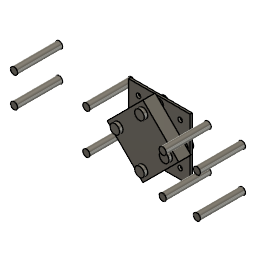
BGD_AIO_ENVELOPE_R3_NOT_FOR_FABRICATION (Autodesk Fusion 360 design; units mm, degrees)
part number: 2026-09-05-21-45-48-838
part number: 2026-09-05-21-45-49-225
part number: 2026-09-05-21-45-49-322
part number: 2026-09-05-21-45-49-390
part number: 2026-09-05-21-45-49-432
part number: 2026-09-05-21-45-49-478
part number: 2026-09-05-21-45-49-524
part number: 2026-09-05-21-45-49-562
part number: 2026-09-05-21-45-49-626
part number: 2026-09-05-21-45-49-709
part number: 2026-09-05-21-45-49-758
part number: 2026-09-05-21-45-49-811
part number: 2026-09-05-21-45-49-877
part number: 2026-09-05-21-45-49-921
part number: 2026-09-05-21-45-49-965
part number: 2026-09-05-21-45-50-016
part number: 2026-09-05-21-45-50-060
part number: 2026-09-05-21-45-50-111
part number: 2026-09-05-21-45-50-153
part number: 2026-09-05-21-45-50-197
part number: 2026-09-05-21-45-50-263
part number: 2026-09-05-21-45-50-331
part number: 2026-09-05-21-45-50-419
part number: 2026-09-05-21-45-50-495
part number: 2026-09-05-21-45-50-578
part number: 2026-09-05-21-45-50-662
part number: 2026-09-05-21-45-50-760
part number: 2026-09-05-21-45-50-872
Autodesk Fusion 360 part; units mm, degrees
sketch "Sketch1" plane through (0, 0, 0) normal (0, 0, 1) x (1, 0, 0) in component "R3_45mm_ADAPTER_NOMINAL_DRILLING_HOLD"
  line L0 (-22.5, -22.5) -> (22.5, -22.5)
  line L1 (22.5, -22.5) -> (22.5, 22.5)
  line L2 (22.5, 22.5) -> (-22.5, 22.5)
  line L3 (-22.5, 22.5) -> (-22.5, -22.5)
  circle A0 centre (-15.25, -15.25) radius 1.6
  circle A1 centre (-15.25, 15.25) radius 1.6
  circle A2 centre (15.25, -15.25) radius 1.6
  circle A3 centre (15.25, 15.25) radius 1.6
  circle A4 centre (18.0312, 0) radius 1.6
  circle A5 centre (-18.0312, 0) radius 1.6
  circle A6 centre (0, 18.0312) radius 1.6
  circle A7 centre (0, -18.0312) radius 1.6
extrude "Extrude1" add sketch "Sketch1" along normal blind 1.6 makes body 1 in component "R3_45mm_ADAPTER_NOMINAL_DRILLING_HOLD"
sketch "Sketch1 (2)" plane through (0, 0, 0) normal (0, 0, 1) x (1, 0, 0) in component "AIO_MAX_37x37x9_CLASS4_ENVELOPE"
  line L0 (-18.5, -18.5) -> (18.5, -18.5)
  line L1 (18.5, -18.5) -> (18.5, 18.5)
  line L2 (18.5, 18.5) -> (-18.5, 18.5)
  line L3 (-18.5, 18.5) -> (-18.5, -18.5)
  circle A0 centre (-12.75, -12.75) radius 1.5
  circle A1 centre (-12.75, 12.75) radius 1.5
  circle A2 centre (12.75, -12.75) radius 1.5
  circle A3 centre (12.75, 12.75) radius 1.5
extrude "Extrude1'" add sketch "Sketch1 (2)" along normal blind 9 separate body makes body 2 in component "AIO_MAX_37x37x9_CLASS4_ENVELOPE"
sketch "Sketch1 (3)" plane through (0, 0, 0) normal (0, 0, 1) x (1, 0, 0) in component "ISOLATOR_0_OD6_RISE3_CONTRACT_ONLY"
  circle A0 centre (0, 0) radius 3
extrude "Extrude1''" add sketch "Sketch1 (3)" along normal blind 3 separate body makes body 3 in component "ISOLATOR_0_OD6_RISE3_CONTRACT_ONLY"
sketch "Sketch1 (4)" plane through (0, 0, 0) normal (0, 0, 1) x (1, 0, 0) in component "FASTENER_TOP_0_PROJECTION_CONTRACT_ONLY"
  circle A0 centre (0, 0) radius 3.5
extrude "Extrude1'''" add sketch "Sketch1 (4)" along normal blind 2.5 separate body makes body 4 in component "FASTENER_TOP_0_PROJECTION_CONTRACT_ONLY"
sketch "Sketch1 (5)" plane through (0, 0, 0) normal (0, 0, 1) x (1, 0, 0) in component "FASTENER_UNDER_0_PROJECTION_CONTRACT_ONLY"
  circle A0 centre (0, 0) radius 3.5
extrude "Extrude1''''" add sketch "Sketch1 (5)" along normal blind 2 separate body makes body 5 in component "FASTENER_UNDER_0_PROJECTION_CONTRACT_ONLY"
sketch "Sketch1 (6)" plane through (0, 0, 0) normal (0, 0, 1) x (1, 0, 0) in component "ISOLATOR_1_OD6_RISE3_CONTRACT_ONLY"
  circle A0 centre (0, 0) radius 3
extrude "Extrude1'''''" add sketch "Sketch1 (6)" along normal blind 3 separate body makes body 6 in component "ISOLATOR_1_OD6_RISE3_CONTRACT_ONLY"
sketch "Sketch1 (7)" plane through (0, 0, 0) normal (0, 0, 1) x (1, 0, 0) in component "FASTENER_TOP_1_PROJECTION_CONTRACT_ONLY"
  circle A0 centre (0, 0) radius 3.5
extrude "Extrude1''''''" add sketch "Sketch1 (7)" along normal blind 2.5 separate body makes body 7 in component "FASTENER_TOP_1_PROJECTION_CONTRACT_ONLY"
sketch "Sketch1 (8)" plane through (0, 0, 0) normal (0, 0, 1) x (1, 0, 0) in component "FASTENER_UNDER_1_PROJECTION_CONTRACT_ONLY"
  circle A0 centre (0, 0) radius 3.5
extrude "Extrude1'''''''" add sketch "Sketch1 (8)" along normal blind 2 separate body makes body 8 in component "FASTENER_UNDER_1_PROJECTION_CONTRACT_ONLY"
sketch "Sketch1 (9)" plane through (0, 0, 0) normal (0, 0, 1) x (1, 0, 0) in component "ISOLATOR_2_OD6_RISE3_CONTRACT_ONLY"
  circle A0 centre (0, 0) radius 3
extrude "Extrude1''''''''" add sketch "Sketch1 (9)" along normal blind 3 separate body makes body 9 in component "ISOLATOR_2_OD6_RISE3_CONTRACT_ONLY"
sketch "Sketch1 (10)" plane through (0, 0, 0) normal (0, 0, 1) x (1, 0, 0) in component "FASTENER_TOP_2_PROJECTION_CONTRACT_ONLY"
  circle A0 centre (0, 0) radius 3.5
extrude "Extrude1'''''''''" add sketch "Sketch1 (10)" along normal blind 2.5 separate body makes body 10 in component "FASTENER_TOP_2_PROJECTION_CONTRACT_ONLY"
sketch "Sketch1 (11)" plane through (0, 0, 0) normal (0, 0, 1) x (1, 0, 0) in component "FASTENER_UNDER_2_PROJECTION_CONTRACT_ONLY"
  circle A0 centre (0, 0) radius 3.5
extrude "Extrude1''''''''''" add sketch "Sketch1 (11)" along normal blind 2 separate body makes body 11 in component "FASTENER_UNDER_2_PROJECTION_CONTRACT_ONLY"
sketch "Sketch1 (12)" plane through (0, 0, 0) normal (0, 0, 1) x (1, 0, 0) in component "ISOLATOR_3_OD6_RISE3_CONTRACT_ONLY"
  circle A0 centre (0, 0) radius 3
extrude "Extrude1'''''''''''" add sketch "Sketch1 (12)" along normal blind 3 separate body makes body 12 in component "ISOLATOR_3_OD6_RISE3_CONTRACT_ONLY"
sketch "Sketch1 (13)" plane through (0, 0, 0) normal (0, 0, 1) x (1, 0, 0) in component "FASTENER_TOP_3_PROJECTION_CONTRACT_ONLY"
  circle A0 centre (0, 0) radius 3.5
extrude "Extrude1''''''''''''" add sketch "Sketch1 (13)" along normal blind 2.5 separate body makes body 13 in component "FASTENER_TOP_3_PROJECTION_CONTRACT_ONLY"
sketch "Sketch1 (14)" plane through (0, 0, 0) normal (0, 0, 1) x (1, 0, 0) in component "FASTENER_UNDER_3_PROJECTION_CONTRACT_ONLY"
  circle A0 centre (0, 0) radius 3.5
extrude "Extrude1'''''''''''''" add sketch "Sketch1 (14)" along normal blind 2 separate body makes body 14 in component "FASTENER_UNDER_3_PROJECTION_CONTRACT_ONLY"
sketch "Sketch1 (15)" plane through (0, 0, 0) normal (0, 0, 1) x (1, 0, 0) in component "FRAME_SUPPORT_0_OD5_2_ENVELOPE"
  circle A0 centre (0, 0) radius 2.6
extrude "Extrude1''''''''''''''" add sketch "Sketch1 (15)" along normal blind 33 separate body makes body 15 in component "FRAME_SUPPORT_0_OD5_2_ENVELOPE"
sketch "Sketch1 (16)" plane through (0, 0, 0) normal (0, 0, 1) x (1, 0, 0) in component "FRAME_SUPPORT_1_OD5_2_ENVELOPE"
  circle A0 centre (0, 0) radius 2.6
extrude "Extrude1'''''''''''''''" add sketch "Sketch1 (16)" along normal blind 33 separate body makes body 16 in component "FRAME_SUPPORT_1_OD5_2_ENVELOPE"
sketch "Sketch1 (17)" plane through (0, 0, 0) normal (0, 0, 1) x (1, 0, 0) in component "FRAME_SUPPORT_2_OD5_2_ENVELOPE"
  circle A0 centre (0, 0) radius 2.6
extrude "Extrude1''''''''''''''''" add sketch "Sketch1 (17)" along normal blind 33 separate body makes body 17 in component "FRAME_SUPPORT_2_OD5_2_ENVELOPE"
sketch "Sketch1 (18)" plane through (0, 0, 0) normal (0, 0, 1) x (1, 0, 0) in component "FRAME_SUPPORT_3_OD5_2_ENVELOPE"
  circle A0 centre (0, 0) radius 2.6
extrude "Extrude1'''''''''''''''''" add sketch "Sketch1 (18)" along normal blind 33 separate body makes body 18 in component "FRAME_SUPPORT_3_OD5_2_ENVELOPE"
sketch "Sketch1 (19)" plane through (0, 0, 0) normal (0, 0, 1) x (1, 0, 0) in component "FRAME_SUPPORT_4_OD5_2_ENVELOPE"
  circle A0 centre (0, 0) radius 2.6
extrude "Extrude1''''''''''''''''''" add sketch "Sketch1 (19)" along normal blind 33 separate body makes body 19 in component "FRAME_SUPPORT_4_OD5_2_ENVELOPE"
sketch "Sketch1 (20)" plane through (0, 0, 0) normal (0, 0, 1) x (1, 0, 0) in component "FRAME_SUPPORT_5_OD5_2_ENVELOPE"
  circle A0 centre (0, 0) radius 2.6
extrude "Extrude1'''''''''''''''''''" add sketch "Sketch1 (20)" along normal blind 33 separate body makes body 20 in component "FRAME_SUPPORT_5_OD5_2_ENVELOPE"
sketch "Sketch1 (21)" plane through (0, 0, 0) normal (0, 0, 1) x (1, 0, 0) in component "FRAME_SUPPORT_6_OD5_2_ENVELOPE"
  circle A0 centre (0, 0) radius 2.6
extrude "Extrude1''''''''''''''''''''" add sketch "Sketch1 (21)" along normal blind 33 separate body makes body 21 in component "FRAME_SUPPORT_6_OD5_2_ENVELOPE"
sketch "Sketch1 (22)" plane through (0, 0, 0) normal (0, 0, 1) x (1, 0, 0) in component "FRAME_SUPPORT_7_OD5_2_ENVELOPE"
  circle A0 centre (0, 0) radius 2.6
extrude "Extrude1'''''''''''''''''''''" add sketch "Sketch1 (22)" along normal blind 33 separate body makes body 22 in component "FRAME_SUPPORT_7_OD5_2_ENVELOPE"
sketch "Sketch1 (23)" plane through (0, 0, 0) normal (0, 0, 1) x (1, 0, 0) in component "LOCAL_P_PLANE_REFERENCE_NOT_FULL_FRAME"
  line L0 (-25, -25) -> (25, -25)
  line L1 (25, -25) -> (25, 25)
  line L2 (25, 25) -> (-25, 25)
  line L3 (-25, 25) -> (-25, -25)
extrude "Extrude1''''''''''''''''''''''" add sketch "Sketch1 (23)" along normal blind 0.2 separate body makes body 23 in component "LOCAL_P_PLANE_REFERENCE_NOT_FULL_FRAME"
sketch "Sketch1 (24)" plane through (0, 0, 0) normal (0, 0, 1) x (1, 0, 0) in component "BOTTOM_CONFLICT_THICKNESS_SWEEP_1_85_TO_2_65_NOT_PLACEMENT"
  line L0 (-25, -25) -> (25, -25)
  line L1 (25, -25) -> (25, 25)
  line L2 (25, 25) -> (-25, 25)
  line L3 (-25, 25) -> (-25, -25)
extrude "Extrude1'''''''''''''''''''''''" add sketch "Sketch1 (24)" along normal blind 0.8 separate body makes body 24 in component "BOTTOM_CONFLICT_THICKNESS_SWEEP_1_85_TO_2_65_NOT_PLACEMENT"
sketch "Sketch1 (25)" plane through (0, 0, 0) normal (0, 0, 1) x (1, 0, 0) in component "BAY_CEILING_MIN21_25_CONDITIONAL_TOPOLOGY_B"
  line L0 (-35, -30) -> (35, -30)
  line L1 (35, -30) -> (35, 30)
  line L2 (35, 30) -> (-35, 30)
  line L3 (-35, 30) -> (-35, -30)
extrude "Extrude1''''''''''''''''''''''''" add sketch "Sketch1 (25)" along normal blind 0.2 separate body makes body 25 in component "BAY_CEILING_MIN21_25_CONDITIONAL_TOPOLOGY_B"
sketch "Sketch1 (26)" plane through (0, 0, 0) normal (0, 0, 1) x (1, 0, 0) in component "USB_SD_ALL_SIDE12_TRIAL_KEEP_OUT_NOT_REAL_CONNECTOR"
  line L0 (-30.5, -30.5) -> (30.5, -30.5)
  line L1 (30.5, -30.5) -> (30.5, 30.5)
  line L2 (30.5, 30.5) -> (-30.5, 30.5)
  line L3 (-30.5, 30.5) -> (-30.5, -30.5)
extrude "Extrude1'''''''''''''''''''''''''" add sketch "Sketch1 (26)" along normal blind 12 separate body makes body 26 in component "USB_SD_ALL_SIDE12_TRIAL_KEEP_OUT_NOT_REAL_CONNECTOR"
sketch "Sketch1 (27)" plane through (0, 0, 0) normal (0, 0, 1) x (1, 0, 0) in component "WIRE_BEND_R36_OD6_PLUS2_KEEP_OUT_NO_ROUTE"
  circle A0 centre (0, 0) radius 41
extrude "Extrude1''''''''''''''''''''''''''" add sketch "Sketch1 (27)" along normal blind 6 separate body makes body 27 in component "WIRE_BEND_R36_OD6_PLUS2_KEEP_OUT_NO_ROUTE"
component "R3_45mm_ADAPTER_NOMINAL_DRILLING_HOLD" placed x (1, 0, 0) y (0, 1, 0) z (0, 0, 1) at (0, 0, 3.3)
component "AIO_MAX_37x37x9_CLASS4_ENVELOPE" placed x (0.707107, 0.707107, 0) y (-0.707107, 0.707107, 0) z (0, 0, 1) at (0, 0, 7.9)
component "ISOLATOR_0_OD6_RISE3_CONTRACT_ONLY" placed x (1, 0, 0) y (0, 1, 0) z (0, 0, 1) at (18.0312, 0, 4.9)
component "FASTENER_TOP_0_PROJECTION_CONTRACT_ONLY" placed x (1, 0, 0) y (0, 1, 0) z (0, 0, 1) at (18.0312, 0, 16.9)
component "FASTENER_UNDER_0_PROJECTION_CONTRACT_ONLY" placed x (1, 0, 0) y (0, 1, 0) z (0, 0, 1) at (18.0312, 0, 1.3)
component "ISOLATOR_1_OD6_RISE3_CONTRACT_ONLY" placed x (1, 0, 0) y (0, 1, 0) z (0, 0, 1) at (-18.0312, 0, 4.9)
component "FASTENER_TOP_1_PROJECTION_CONTRACT_ONLY" placed x (1, 0, 0) y (0, 1, 0) z (0, 0, 1) at (-18.0312, 0, 16.9)
component "FASTENER_UNDER_1_PROJECTION_CONTRACT_ONLY" placed x (1, 0, 0) y (0, 1, 0) z (0, 0, 1) at (-18.0312, 0, 1.3)
component "ISOLATOR_2_OD6_RISE3_CONTRACT_ONLY" placed x (1, 0, 0) y (0, 1, 0) z (0, 0, 1) at (0, 18.0312, 4.9)
component "FASTENER_TOP_2_PROJECTION_CONTRACT_ONLY" placed x (1, 0, 0) y (0, 1, 0) z (0, 0, 1) at (0, 18.0312, 16.9)
component "FASTENER_UNDER_2_PROJECTION_CONTRACT_ONLY" placed x (1, 0, 0) y (0, 1, 0) z (0, 0, 1) at (0, 18.0312, 1.3)
component "ISOLATOR_3_OD6_RISE3_CONTRACT_ONLY" placed x (1, 0, 0) y (0, 1, 0) z (0, 0, 1) at (0, -18.0312, 4.9)
component "FASTENER_TOP_3_PROJECTION_CONTRACT_ONLY" placed x (1, 0, 0) y (0, 1, 0) z (0, 0, 1) at (0, -18.0312, 16.9)
component "FASTENER_UNDER_3_PROJECTION_CONTRACT_ONLY" placed x (1, 0, 0) y (0, 1, 0) z (0, 0, 1) at (0, -18.0312, 1.3)
component "FRAME_SUPPORT_0_OD5_2_ENVELOPE" placed x (1, 0, 0) y (0, 1, 0) z (0, 0, 1) at (52.8833, -14.6, -2.65)
component "FRAME_SUPPORT_1_OD5_2_ENVELOPE" placed x (1, 0, 0) y (0, 1, 0) z (0, 0, 1) at (27.8833, -14.6, -2.65)
component "FRAME_SUPPORT_2_OD5_2_ENVELOPE" placed x (1, 0, 0) y (0, 1, 0) z (0, 0, 1) at (-27.8836, -14.6, -2.65)
component "FRAME_SUPPORT_3_OD5_2_ENVELOPE" placed x (1, 0, 0) y (0, 1, 0) z (0, 0, 1) at (52.8833, 14.6, -2.65)
component "FRAME_SUPPORT_4_OD5_2_ENVELOPE" placed x (1, 0, 0) y (0, 1, 0) z (0, 0, 1) at (27.8833, 14.6, -2.65)
component "FRAME_SUPPORT_5_OD5_2_ENVELOPE" placed x (1, 0, 0) y (0, 1, 0) z (0, 0, 1) at (-27.8836, 14.6, -2.65)
component "FRAME_SUPPORT_6_OD5_2_ENVELOPE" placed x (1, 0, 0) y (0, 1, 0) z (0, 0, 1) at (-80.7544, -11, -2.65)
component "FRAME_SUPPORT_7_OD5_2_ENVELOPE" placed x (1, 0, 0) y (0, 1, 0) z (0, 0, 1) at (-80.7544, 11, -2.65)
component "LOCAL_P_PLANE_REFERENCE_NOT_FULL_FRAME" placed x (1, 0, 0) y (0, 1, 0) z (0, 0, 1) at (0, 0, -0.2)
component "BOTTOM_CONFLICT_THICKNESS_SWEEP_1_85_TO_2_65_NOT_PLACEMENT" placed x (1, 0, 0) y (0, 1, 0) z (0, 0, 1) at (0, 0, -10.65)
component "BAY_CEILING_MIN21_25_CONDITIONAL_TOPOLOGY_B" placed x (1, 0, 0) y (0, 1, 0) z (0, 0, 1) at (0, 0, 21.25)
component "USB_SD_ALL_SIDE12_TRIAL_KEEP_OUT_NOT_REAL_CONNECTOR" placed x (0.707107, 0.707107, 0) y (-0.707107, 0.707107, 0) z (0, 0, 1) at (0, 0, 7.9)
component "WIRE_BEND_R36_OD6_PLUS2_KEEP_OUT_NO_ROUTE" placed x (1, 0, 0) y (0, 1, 0) z (0, 0, 1) at (0, 0, -45)
named bodies: "R3_45mm_ADAPTER_NOMINAL_DRILLING_HOLD", "AIO_MAX_37x37x9_CLASS4_ENVELOPE", "ISOLATOR_0_OD6_RISE3_CONTRACT_ONLY", "FASTENER_TOP_0_PROJECTION_CONTRACT_ONLY", "FASTENER_UNDER_0_PROJECTION_CONTRACT_ONLY", "ISOLATOR_1_OD6_RISE3_CONTRACT_ONLY", "FASTENER_TOP_1_PROJECTION_CONTRACT_ONLY", "FASTENER_UNDER_1_PROJECTION_CONTRACT_ONLY", "ISOLATOR_2_OD6_RISE3_CONTRACT_ONLY", "FASTENER_TOP_2_PROJECTION_CONTRACT_ONLY", "FASTENER_UNDER_2_PROJECTION_CONTRACT_ONLY", "ISOLATOR_3_OD6_RISE3_CONTRACT_ONLY", "FASTENER_TOP_3_PROJECTION_CONTRACT_ONLY", "FASTENER_UNDER_3_PROJECTION_CONTRACT_ONLY", "FRAME_SUPPORT_0_OD5_2_ENVELOPE", "FRAME_SUPPORT_1_OD5_2_ENVELOPE", "FRAME_SUPPORT_2_OD5_2_ENVELOPE", "FRAME_SUPPORT_3_OD5_2_ENVELOPE", "FRAME_SUPPORT_4_OD5_2_ENVELOPE", "FRAME_SUPPORT_5_OD5_2_ENVELOPE", "FRAME_SUPPORT_6_OD5_2_ENVELOPE", "FRAME_SUPPORT_7_OD5_2_ENVELOPE", "LOCAL_P_PLANE_REFERENCE_NOT_FULL_FRAME", "BOTTOM_CONFLICT_THICKNESS_SWEEP_1_85_TO_2_65_NOT_PLACEMENT", "BAY_CEILING_MIN21_25_CONDITIONAL_TOPOLOGY_B", "USB_SD_ALL_SIDE12_TRIAL_KEEP_OUT_NOT_REAL_CONNECTOR", "WIRE_BEND_R36_OD6_PLUS2_KEEP_OUT_NO_ROUTE"
